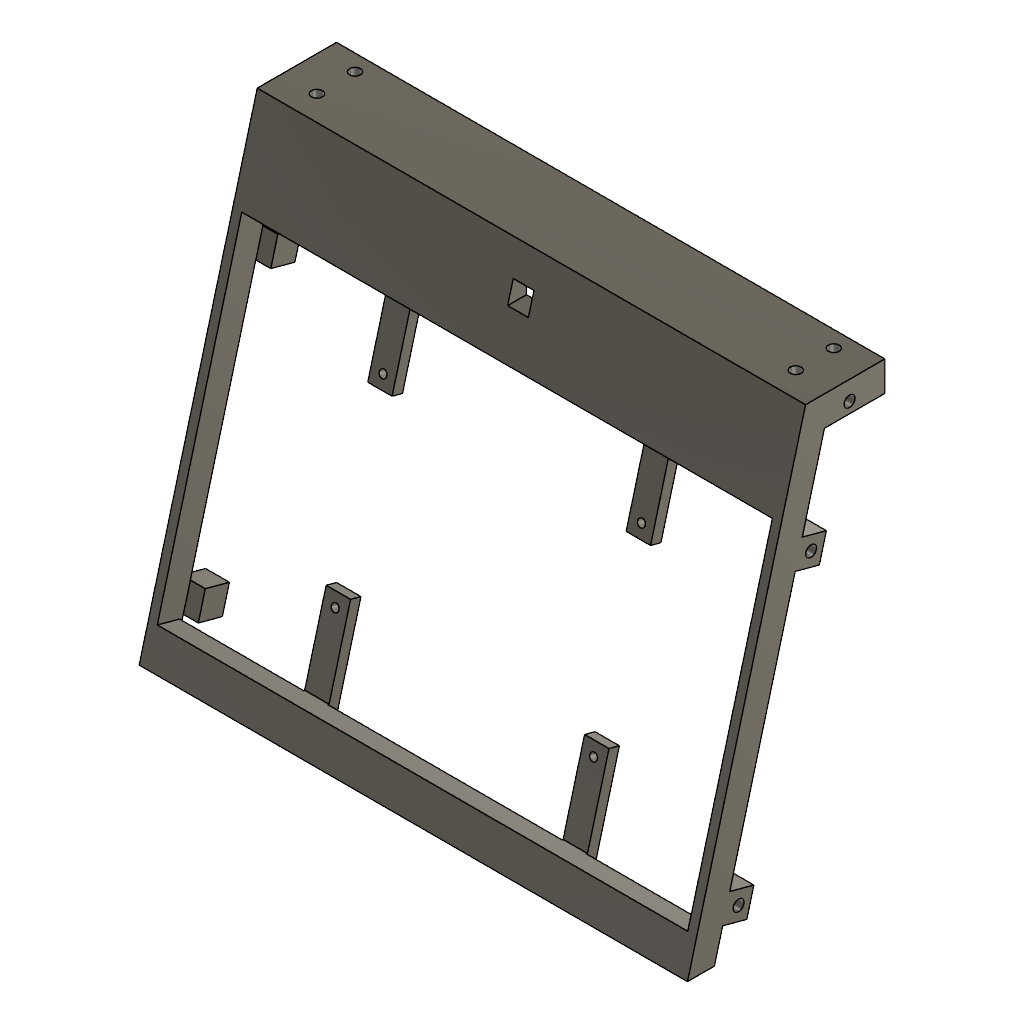
Bezel (Autodesk Fusion 360 design; units mm, degrees)
part number: 2026-10-19-10-28-38-784
Autodesk Fusion 360 part; units mm, degrees
sketch "front_slab" plane through (0, 0, 0) normal (1, 0, 0) x (0, 0, -1)
  line L0 (-9, 2.4115) -> (-171, 45.8193)
  line L1 (-171, 45.8193) -> (-171, 54.6192)
  line L2 (-171, 54.6192) -> (-9, 11.2114)
  line L3 (-9, 11.2114) -> (-9, 2.4115)
extrude "front_slab (1)" add sketch "front_slab" along normal blind 201.6 from surface at -100.8 makes body 1
sketch "display_opening" plane through (0, 0, 0) normal (1, 0, 0) x (0, 0, -1)
  line L0 (-12.503, 40.206) -> (-128.4141, 71.2643)
  line L1 (-128.4141, 71.2643) -> (-138.7669, 32.6273)
  line L2 (-138.7669, 32.6273) -> (-22.8558, 1.569)
  line L3 (-22.8558, 1.569) -> (-12.503, 40.206)
extrude "display_opening (1)" cut sketch "display_opening" along normal blind 195 from surface at -97.5 bodies 1
sketch "rail_R" plane through (0, 0, 0) normal (1, 0, 0) x (0, 0, -1)
  line L0 (-9, 12.3502) -> (-168, 54.9541)
  line L1 (-168, 54.9541) -> (-168, 53.8153)
  line L2 (-168, 53.8153) -> (-9, 11.2114)
  line L3 (-9, 11.2114) -> (-9, 12.3502)
extrude "rail_R (1)" add sketch "rail_R" along normal blind 3.3 from surface at 97.5 bodies 1
sketch "rail_L" plane through (0, 0, 0) normal (1, 0, 0) x (0, 0, -1)
  line L0 (-9, 12.3502) -> (-168, 54.9541)
  line L1 (-168, 54.9541) -> (-168, 53.8153)
  line L2 (-168, 53.8153) -> (-9, 11.2114)
  line L3 (-9, 11.2114) -> (-9, 12.3502)
extrude "rail_L (1)" add sketch "rail_L" along normal blind 3.3 from surface at -100.8 bodies 1
sketch "top_plate" plane through (0, 0, 0) normal (1, 0, 0) x (0, 0, -1)
  line L0 (-168, 45.0155) -> (-171, 45.8193)
  line L1 (-171, 45.8193) -> (-171, 75)
  line L2 (-171, 75) -> (-168, 75)
  line L3 (-168, 75) -> (-168, 45.0155)
extrude "top_plate (1)" add sketch "top_plate" along normal blind 201.6 from surface at -100.8 bodies 1
sketch "rail_boss" plane through (0, 0, 0) normal (1, 0, 0) x (0, 0, -1)
  line L0 (-17.9137, 24.2632) -> (-27.573, 26.8513)
  line L1 (-27.573, 26.8513) -> (-29.9541, 17.9648)
  line L2 (-29.9541, 17.9648) -> (-20.2949, 15.3766)
  line L3 (-20.2949, 15.3766) -> (-17.9137, 24.2632)
extrude "rail_boss (1)" add sketch "rail_boss" along normal blind 8.8 from surface at 92 bodies 1
sketch "rail_boss (1)" plane through (0, 0, 0) normal (1, 0, 0) x (0, 0, -1)
  line L0 (-17.9137, 24.2632) -> (-27.573, 26.8513)
  line L1 (-27.573, 26.8513) -> (-29.9541, 17.9648)
  line L2 (-29.9541, 17.9648) -> (-20.2949, 15.3766)
  line L3 (-20.2949, 15.3766) -> (-17.9137, 24.2632)
extrude "rail_boss (2)" add sketch "rail_boss (1)" against normal blind 8.8 from surface at -92 bodies 1
sketch "rail_boss (2)" plane through (0, 0, 0) normal (1, 0, 0) x (0, 0, -1)
  line L0 (-117.4041, 50.9215) -> (-127.0633, 53.5097)
  line L1 (-127.0633, 53.5097) -> (-129.4445, 44.6232)
  line L2 (-129.4445, 44.6232) -> (-119.7852, 42.035)
  line L3 (-119.7852, 42.035) -> (-117.4041, 50.9215)
extrude "rail_boss (3)" add sketch "rail_boss (2)" along normal blind 8.8 from surface at 92 bodies 1
sketch "rail_boss (3)" plane through (0, 0, 0) normal (1, 0, 0) x (0, 0, -1)
  line L0 (-117.4041, 50.9215) -> (-127.0633, 53.5097)
  line L1 (-127.0633, 53.5097) -> (-129.4445, 44.6232)
  line L2 (-129.4445, 44.6232) -> (-119.7852, 42.035)
  line L3 (-119.7852, 42.035) -> (-117.4041, 50.9215)
extrude "rail_boss (4)" add sketch "rail_boss (3)" against normal blind 8.8 from surface at -92 bodies 1
sketch "top_side_lip" plane through (0, 0, 0) normal (0, 0, 1) x (1, 0, 0)
  line L0 (93, 50) -> (100.8, 50)
  line L1 (100.8, 50) -> (100.8, 75)
  line L2 (100.8, 75) -> (93, 75)
  line L3 (93, 75) -> (93, 50)
extrude "top_side_lip (1)" add sketch "top_side_lip" along normal blind 8 from surface at 160 bodies 1
sketch "top_rear_boss" plane through (0, 0, 0) normal (0, 0, 1) x (1, 0, 0)
  line L0 (55, 67) -> (65, 67)
  line L1 (65, 67) -> (65, 75)
  line L2 (65, 75) -> (55, 75)
  line L3 (55, 75) -> (55, 67)
extrude "top_rear_boss (1)" add sketch "top_rear_boss" along normal blind 10 from surface at 158 bodies 1
sketch "top_side_lip (1)" plane through (0, 0, 0) normal (0, 0, 1) x (1, 0, 0)
  line L0 (-100.8, 50) -> (-93, 50)
  line L1 (-93, 50) -> (-93, 75)
  line L2 (-93, 75) -> (-100.8, 75)
  line L3 (-100.8, 75) -> (-100.8, 50)
extrude "top_side_lip (2)" add sketch "top_side_lip (1)" along normal blind 8 from surface at 160 bodies 1
sketch "top_rear_boss (1)" plane through (0, 0, 0) normal (0, 0, 1) x (1, 0, 0)
  line L0 (-65, 67) -> (-55, 67)
  line L1 (-55, 67) -> (-55, 75)
  line L2 (-55, 75) -> (-65, 75)
  line L3 (-65, 75) -> (-65, 67)
extrude "top_rear_boss (2)" add sketch "top_rear_boss (1)" along normal blind 10 from surface at 158 bodies 1
sketch "dslr_boss" plane through (0, 0, 0) normal (0, 0, 1) x (1, 0, 0)
  circle A0 centre (-88, 55) radius 4.5
  circle A1 centre (88, 55) radius 4.5
  circle A2 centre (-88, 69) radius 4.5
  circle A3 centre (88, 69) radius 4.5
extrude "dslr_boss (1)" add sketch "dslr_boss" along normal blind 8 from surface at 160 bodies 1
sketch "disp_strut" plane through (0, 0, 0) normal (1, 0, 0) x (0, 0, -1)
  line L0 (-11.7004, 16.5419) -> (-47.826, 26.2218)
  line L1 (-47.826, 26.2218) -> (-48.8613, 22.3581)
  line L2 (-48.8613, 22.3581) -> (-12.7357, 12.6782)
  line L3 (-12.7357, 12.6782) -> (-11.7004, 16.5419)
extrude "disp_strut (1)" add sketch "disp_strut" along normal blind 9 from surface at -52 bodies 1 makes body 2
sketch "disp_strut_root" plane through (0, 0, 0) normal (1, 0, 0) x (0, 0, -1)
  line L0 (-12.6839, 12.8714) -> (-19.3488, 14.6573)
  line L1 (-19.3488, 14.6573) -> (-19.5429, 13.9328)
  line L2 (-19.5429, 13.9328) -> (-12.878, 12.147)
  line L3 (-12.878, 12.147) -> (-12.6839, 12.8714)
extrude "disp_strut_root (1)" add sketch "disp_strut_root" along normal blind 9 from surface at -52 bodies 1
sketch "disp_strut (1)" plane through (0, 0, 0) normal (1, 0, 0) x (0, 0, -1)
  line L0 (-11.7004, 16.5419) -> (-47.826, 26.2218)
  line L1 (-47.826, 26.2218) -> (-48.8613, 22.3581)
  line L2 (-48.8613, 22.3581) -> (-12.7357, 12.6782)
  line L3 (-12.7357, 12.6782) -> (-11.7004, 16.5419)
extrude "disp_strut (2)" add sketch "disp_strut (1)" along normal blind 9 from surface at 43 bodies 1 makes body 3
sketch "disp_strut_root (1)" plane through (0, 0, 0) normal (1, 0, 0) x (0, 0, -1)
  line L0 (-12.6839, 12.8714) -> (-19.3488, 14.6573)
  line L1 (-19.3488, 14.6573) -> (-19.5429, 13.9328)
  line L2 (-19.5429, 13.9328) -> (-12.878, 12.147)
  line L3 (-12.878, 12.147) -> (-12.6839, 12.8714)
extrude "disp_strut_root (2)" add sketch "disp_strut_root (1)" along normal blind 9 from surface at 43 bodies 1
sketch "disp_strut (2)" plane through (0, 0, 0) normal (1, 0, 0) x (0, 0, -1)
  line L0 (-104.8157, 41.4921) -> (-144.9016, 52.2331)
  line L1 (-144.9016, 52.2331) -> (-145.9369, 48.3694)
  line L2 (-145.9369, 48.3694) -> (-105.8509, 37.6284)
  line L3 (-105.8509, 37.6284) -> (-104.8157, 41.4921)
extrude "disp_strut (3)" add sketch "disp_strut (2)" along normal blind 9 from surface at -52 bodies 1 makes body 4
sketch "disp_strut_root (2)" plane through (0, 0, 0) normal (1, 0, 0) x (0, 0, -1)
  line L0 (-135.2599, 45.7156) -> (-145.8851, 48.5626)
  line L1 (-145.8851, 48.5626) -> (-146.0792, 47.8381)
  line L2 (-146.0792, 47.8381) -> (-135.454, 44.9911)
  line L3 (-135.454, 44.9911) -> (-135.2599, 45.7156)
extrude "disp_strut_root (3)" add sketch "disp_strut_root (2)" along normal blind 9 from surface at -52 bodies 1
sketch "disp_strut (3)" plane through (0, 0, 0) normal (1, 0, 0) x (0, 0, -1)
  line L0 (-104.8157, 41.4921) -> (-144.9016, 52.2331)
  line L1 (-144.9016, 52.2331) -> (-145.9369, 48.3694)
  line L2 (-145.9369, 48.3694) -> (-105.8509, 37.6284)
  line L3 (-105.8509, 37.6284) -> (-104.8157, 41.4921)
extrude "disp_strut (4)" add sketch "disp_strut (3)" along normal blind 9 from surface at 43 bodies 1 makes body 5
sketch "disp_strut_root (3)" plane through (0, 0, 0) normal (1, 0, 0) x (0, 0, -1)
  line L0 (-135.2599, 45.7156) -> (-145.8851, 48.5626)
  line L1 (-145.8851, 48.5626) -> (-146.0792, 47.8381)
  line L2 (-146.0792, 47.8381) -> (-135.454, 44.9911)
  line L3 (-135.454, 44.9911) -> (-135.2599, 45.7156)
extrude "disp_strut_root (4)" add sketch "disp_strut_root (3)" along normal blind 9 from surface at 43 bodies 1
combine "combine_struts" operation add target body 1 tool bodies 2 3 4 5
ref_plane "WorkPlane1" through (12.125, 0, 0) normal (0, 0.965926, -0.258819) x (1, 0, 0)
sketch "disp_screw_holes" plane through (0, 0, 0) normal (0, 0.965926, -0.258819) x (1, 0, 0)
  circle A0 centre (-47.5, -48.4831) radius 1.4
  circle A1 centre (47.5, -48.4831) radius 1.4
  circle A2 centre (-47.5, -116.4831) radius 1.4
  circle A3 centre (47.5, -116.4831) radius 1.4
extrude "disp_screw_holes (1)" cut sketch "disp_screw_holes" against normal blind 5 from surface at 13.45 bodies 1
sketch "camera_block" plane through (0, 0, 0) normal (1, 0, 0) x (0, 0, -1)
  line L0 (-138.5, 37.311) -> (-166.5, 44.8135)
  line L1 (-166.5, 44.8135) -> (-166.5, 47.8719)
  line L2 (-166.5, 47.8719) -> (-138.5, 47.8719)
  line L3 (-138.5, 47.8719) -> (-138.5, 37.311)
extrude "camera_block (1)" add sketch "camera_block" along normal blind 32 from surface at -16 bodies 1
sketch "camera_pocket" plane through (0, 0, 0) normal (1, 0, 0) x (0, 0, -1)
  line L0 (-138.5, 47.8719) -> (-166.5, 47.8719)
  line L1 (-166.5, 47.8719) -> (-166.5, 62.8719)
  line L2 (-166.5, 62.8719) -> (-138.5, 62.8719)
  line L3 (-138.5, 62.8719) -> (-138.5, 47.8719)
extrude "camera_pocket (1)" cut sketch "camera_pocket" along normal blind 28 from surface at -14 bodies 1
sketch "lens_hole" plane through (0, 0, 0) normal (0, 1, 0) x (1, 0, 0)
  line L0 (-3.8, -152.7) -> (3.8, -152.7)
  line L1 (3.8, -152.7) -> (3.8, -160.3)
  line L2 (3.8, -160.3) -> (-3.8, -160.3)
  line L3 (-3.8, -160.3) -> (-3.8, -152.7)
extrude "lens_hole (1)" cut sketch "lens_hole" along normal blind 6.5 from surface at 41.8719 bodies 1
sketch "connector_recess" plane through (0, 0, 0) normal (0, 1, 0) x (1, 0, 0)
  line L0 (-12, -139.5) -> (12, -139.5)
  line L1 (12, -139.5) -> (12, -147.5)
  line L2 (12, -147.5) -> (-12, -147.5)
  line L3 (-12, -147.5) -> (-12, -139.5)
extrude "connector_recess (1)" cut sketch "connector_recess" along normal blind 3 from surface at 45.3719 bodies 1
sketch "cam_pilot_M1.5" plane through (0, 0, 0) normal (0, 1, 0) x (1, 0, 0)
  circle A0 centre (-10, -149) radius 0.6
  circle A1 centre (10, -149) radius 0.6
  circle A2 centre (-10, -163) radius 0.6
  circle A3 centre (10, -163) radius 0.6
extrude "cam_pilot_M1.5 (1)" cut sketch "cam_pilot_M1.5" against normal blind 3.5 from surface at 48.3719 bodies 1
sketch "ins_side_R" plane through (0, 0, 0) normal (1, 0, 0) x (0, 0, -1)
  circle A0 centre (-23.908, 21.2106) radius 2
  circle A1 centre (-123.3984, 47.8689) radius 2
  circle A2 centre (-164, 62) radius 2
extrude "ins_side_R (1)" cut sketch "ins_side_R" against normal blind 6.2 from surface at 101 bodies 1
sketch "ins_side_L" plane through (0, 0, 0) normal (1, 0, 0) x (0, 0, -1)
  circle A0 centre (-23.908, 21.2106) radius 2
  circle A1 centre (-123.3984, 47.8689) radius 2
  circle A2 centre (-164, 62) radius 2
extrude "ins_side_L (1)" cut sketch "ins_side_L" along normal blind 6.2 from surface at -101 bodies 1
sketch "ins_base" plane through (0, 0, 0) normal (0, 0, 1) x (1, 0, 0)
  circle A0 centre (-70, 8) radius 2
  circle A1 centre (70, 8) radius 2
extrude "ins_base (1)" cut sketch "ins_base" along normal blind 10.2 from surface at 8.8 bodies 1
sketch "ins_rear_wall" plane through (0, 0, 0) normal (0, 1, 0) x (1, 0, 0)
  circle A0 centre (-60, -164) radius 2
  circle A1 centre (60, -164) radius 2
extrude "ins_rear_wall (1)" cut sketch "ins_rear_wall" against normal blind 6.2 from surface at 75.2 bodies 1
sketch "ins_dslr" plane through (0, 0, 0) normal (0, 0, 1) x (1, 0, 0)
  circle A0 centre (-88, 55) radius 2
  circle A1 centre (88, 55) radius 2
  circle A2 centre (-88, 69) radius 2
  circle A3 centre (88, 69) radius 2
extrude "ins_dslr (1)" cut sketch "ins_dslr" against normal blind 8.2 from surface at 171.2 bodies 1
sketch "lens_hole_through" plane through (0, 0, 0) normal (0, 1, 0) x (1, 0, 0)
  line L0 (-3.8, -152.7) -> (3.8, -152.7)
  line L1 (3.8, -152.7) -> (3.8, -160.3)
  line L2 (3.8, -160.3) -> (-3.8, -160.3)
  line L3 (-3.8, -160.3) -> (-3.8, -152.7)
extrude "lens_hole_through (1)" cut sketch "lens_hole_through" along normal blind 8.456 from surface at 39.9158 bodies 1
equation "d831 = -( 8.80 mm )"
equation "d837 = -( 8.80 mm )"
equation "d881 = -( 5.00 mm )"
equation "d896 = -( 3.50 mm )"
equation "d899 = -( 6.20 mm )"
equation "d908 = -( 6.20 mm )"
equation "d911 = -( 8.20 mm )"
named bodies: "Bezel"
